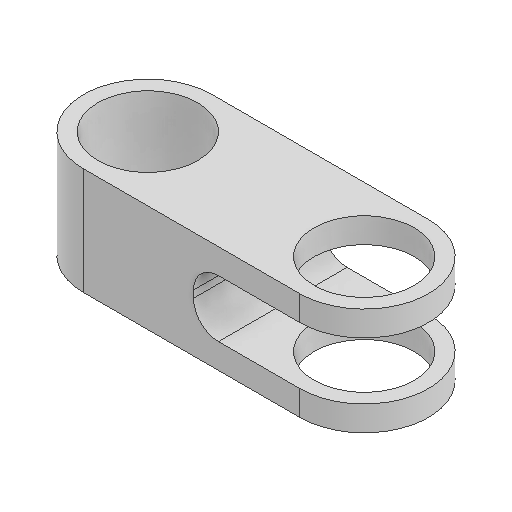
# Autodesk Inventor part: bar_ab
Saved by Autodesk Inventor 2026.1 (Build 301233020, 233B)
## iProperties
Created: 2025-11-26
Part Number: bar_ab
Material: Genérico
Document SubType Name: Modeling
Designer: matia
Density: 1 g/cm^3
Appearance: Valor por defecto
Author: matia
Autodesk Inventor part; units mm, degrees
ref_plane "YZ Plane" through (0, 0, 0) normal (1, 0, 0) x (0, 1, 0)
ref_plane "XZ Plane" through (0, 0, 0) normal (0, 1, 0) x (-1, 0, 0)
ref_plane "XY Plane" through (0, 0, 0) normal (0, 0, 1) x (1, 0, 0)
sketch "Sketch1" plane through (0, 0, 0) normal (0, 1, 0) x (-1, 0, 0)
  circle A0 centre (0, 0) radius 5
  circle A1 centre (-30.3, 0) radius 5
  line L0 (0, 0) -> (-30.3, 0) construction
  line L1 (0, 9) -> (-30.3, 9)
  line L2 (-30.3, -9) -> (0, -9)
  arc A2 (0, -9) -> (0, 9) centre (0, 0) ccw
  arc A3 (-30.3, 9) -> (-30.3, -9) centre (-30.3, 0) ccw
  circle A4 centre (0, 0) radius 7
  circle A5 centre (-30.3, 0) radius 7
  point P0 (-15.15, 0)
  dimension "d_hole" = 10
  dimension "l_a" = 30.3
  dimension "w_ab" = 18
  dimension "d4" = 14
  dimension "d6" = 14
  dimension "d7" = 10
  constraints: 8 end point, 6 centre point, 4 point on circle, 4 tangent, 3 coincident, 1 horizontal, 1 midpoint, 1 parallel
  measures "d_hole" diameter of A0
  measures "l_a" distance of L0.end point (0, 0)
  measures "w_ab" diameter of A3
  measures "d4" diameter of A4
  measures "d6" diameter of A5
  measures "d7" diameter of A1
extrude "Extrusion1" add sketch "Sketch1" along normal blind 3.5 contours A2 L2 A3 L1
sketch "Sketch2" plane through (0, 3.5, 0) normal (0, 1, 0) x (1, 0, 0)
  arc A0 (30.3, -9) -> (30.3, 9) centre (30.3, 0) ccw projected
  line L0 (30.3, 9) -> (0, 9) projected
  arc A1 (0, 9) -> (0, -9) centre (0, 0) ccw projected
  line L1 (0, -9) -> (30.3, -9) projected
  circle A2 centre (30.3, 0) radius 7 projected
  circle A3 centre (0, 0) radius 7 projected
  line L2 (15.4, -9) -> (15.4, 9)
  point P0 (15.15, 9)
  point P1 (15.15, -9)
  point P2 (15.4, 0)
  dimension "d13" = 15.4
  constraints: 3 midpoint, 2 end point, 2 point on line, 1 perpendicular
  measures "d13" distance of point (0, 0) point (15.4, 0)
extrude "Extrusion2" add sketch "Sketch2" along normal blind 4 contours L1 A1 L0 L2
fillet "Fillet1" radius 3.5 1 edges at (15.4, 3.5, 0)
mirror "Mirror1" about plane through (3.2, 7.5, 0) normal (0, 1, 0)
equation "\"d7\" = d_hole"
equation "\"d12\" = t_ab"
equation "\"t_ab\" = 3.5"
body "Solid1"
